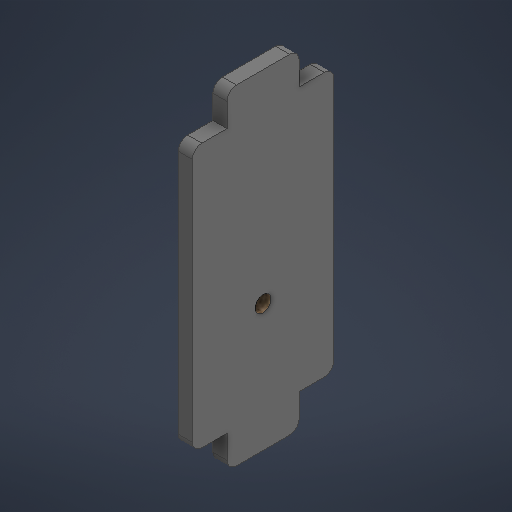
# Autodesk Inventor part: Ir_mount
Saved by Autodesk Inventor 2027.1 (Build 311270010, 270A)
## iProperties
Created: 2026-11-04
Part Number: Ir_mount
Material: MDF Medium Density Fiberboard
Document SubType Name: Modeling
Designer: SDS Scholar
Density: 0.8 g/cm^3
Appearance: Cardboard - Corrugated
Author: SDS Scholar
Autodesk Inventor part; units mm, degrees
ref_plane "YZ Plane" through (0, 0, 0) normal (1, 0, 0) x (0, 1, 0)
ref_plane "XZ Plane" through (0, 0, 0) normal (0, 1, 0) x (-1, 0, 0)
ref_plane "XY Plane" through (0, 0, 0) normal (0, 0, 1) x (1, 0, 0)
sketch "Sketch1" plane through (0, 0, 0) normal (1, 0, 0) x (0, 1, 0)
  line L0 (35, 15) -> (-35, 15)
  line L1 (-35, 15) -> (-35, -15)
  line L2 (-35, -15) -> (35, -15)
  line L3 (35, -15) -> (35, 15)
  point P0 (0, 0)
  point P1 (0, -15)
  point P2 (35, 0)
  dimension "d0" = 70
  dimension "d1" = 30
  constraints: 8 end point, 2 midpoint, 2 parallel, 1 horizontal, 1 horizontal alignment, 1 perpendicular, 1 vertical alignment
  measures "d0" distance of L1.end L2.end
  measures "d1" distance of L2.end L0.start
extrude "Extrusion1" add sketch "Sketch1" along normal blind 3
sketch "Sketch2" plane through (3, 0, 0) normal (1, 0, 0) x (0, 0, -1)
  line L0 (-15, -35) -> (15, -35) projected
  line L1 (15, -35) -> (15, 35) projected
  line L2 (15, 35) -> (-15, 35) projected
  line L3 (-15, 35) -> (-15, -35) projected
  line L4 (15, 28) -> (-15, 28)
  line L5 (-15, -28) -> (15, -28)
  line L6 (-7.65, -35) -> (7.65, -35)
  line L7 (7.65, -35) -> (7.65, -28)
  line L8 (7.65, -28) -> (-7.65, -28)
  line L9 (-7.65, -28) -> (-7.65, -35)
  line L10 (15, 35) -> (-15, 35) projected
  line L11 (-7.65, 28) -> (7.65, 28)
  line L12 (7.65, 28) -> (7.65, 35)
  line L13 (7.65, 35) -> (-7.65, 35)
  line L14 (-7.65, 35) -> (-7.65, 28)
  point P0 (0, -28)
  point P1 (0, -28)
  point P2 (0, 35)
  point P3 (0, 35)
  dimension "d4" = 7
  dimension "d5" = 7
  dimension "d6" = 15.3
  dimension "d7" = 15.3
  constraints: 20 end point, 8 point on line, 4 midpoint, 4 parallel, 3 horizontal, 3 perpendicular, 2 coincident
  measures "d4" distance between parallel lines of L2 L4
  measures "d5" distance between parallel lines of L0 L5
  measures "d6" distance between parallel lines of L7 L9
  measures "d7" distance between parallel lines of L14 L12
extrude "Extrusion2" cut sketch "Sketch2" against normal through all contours L3 L5 L9 L0 | L7 L5 L1 L0 | L3 L2 L14 L4 | L12 L2 L1 L4
sketch "Sketch3" plane through (3, 0, 0) normal (1, 0, 0) x (0, 0, -1)
  line L0 (7.65, -28) -> (15, -28) projected
  line L1 (15, -28) -> (15, 28) projected
  line L2 (15, 28) -> (7.65, 28) projected
  line L3 (7.65, 28) -> (7.65, 35) projected
  line L4 (7.65, 35) -> (-7.65, 35) projected
  line L5 (-7.65, 35) -> (-7.65, 28) projected
  line L6 (-7.65, 28) -> (-15, 28) projected
  line L7 (-15, 28) -> (-15, -28) projected
  line L8 (-15, -28) -> (-7.65, -28) projected
  line L9 (-7.65, -28) -> (-7.65, -35) projected
  line L10 (-7.65, -35) -> (7.65, -35) projected
  line L11 (7.65, -35) -> (7.65, -28) projected
  circle A0 centre (0, -8) radius 1.65
  point P0 (0, 0)
  dimension "d12" = 3.3
  dimension "d24" = 8
  constraints: 1 centre point, 1 vertical alignment
  measures "d12" diameter of A0
  measures "d24" distance of A0.centre point (0, 0)
fillet "Fillet1" radius 2 8 edges at (1.5, 35, 7.65) (1.5, 28, -15) (1.5, 35, -7.65) (1.5, 28, 15) (1.5, -28, 15) (1.5, -35, 7.65) (1.5, -35, -7.65) (1.5, -28, -15)
hole "Hole1" at (3, -8, 0) direction (-1, 0, 0) diameter 3.4 end through all clearance for "Countersunk Flat Head Screw ISO 2009/7046" size "M3" standard "ISO"
body "Solid1"
